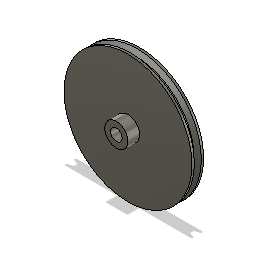
Support moteur (Autodesk Fusion 360 archive; units mm, degrees)
design "PouliePlastique"
Autodesk Fusion 360 part; units mm, degrees
sketch "Esquisse1" plane through (0, 0, 0) normal (1, 0, 0) x (0, 0, -1)
  line L0 (0, 0) -> (33, 0) construction
  line L1 (0, 0) -> (0, 20) construction
  line L2 (-10, 0) -> (-10, 110)
  line L3 (-10, 110) -> (-6, 110)
  line L4 (-6, 110) -> (-3, 100.5)
  line L5 (-3, 100.5) -> (0, 100.5)
  line L6 (3, 100.5) -> (0, 100.5)
  line L7 (10, 0) -> (10, 110)
  line L8 (6, 110) -> (3, 100.5)
  line L9 (10, 110) -> (6, 110)
  line L10 (10, 0) -> (-10, 0)
  point P0 (0, 20)
  dimension "d7" = 110
  dimension "d8" = 4
  dimension "d9" = 100.5
  dimension "d11" = 3
  dimension "d21" = 107.526
  constraint coincident L0.start L1.start
  constraint horizontal L0
  constraint perpendicular L0 L1
  constraint vertical L2
  constraint perpendicular L2 L3
  constraint horizontal L5
  constraint coincident L1 L5.end
  constraint coincident L0 L2.start
  constraint symmetric L0.start L1 origin
  constraint symmetric P0 L1 L1.end
  constraint symmetric L1 L2.start L7.start
  constraint symmetric L1 L2.end L7.end
  constraint symmetric L1 L3.end L8.start
  constraint symmetric L1 L4.end L6.start
  constraint symmetric L1 L5.end L6.end
  measures "d7" distance of L2.start L2.end
  measures "d8" distance of L2.end L3.end
  measures "d9" distance of L2.start L5
  measures "d11" distance of L4.end L5.end
  measures "d21" angle of L4 L5
revolve "Révolution1" add sketch "Esquisse1" angle 360 about axis through (0, 0, 0) along (0, 0, -1)
sketch "Esquisse2" plane through (0, 0, 10) normal (0, 0, 1) x (1, 0, 0)
  circle A0 centre (0, 0) radius 110
  circle A1 centre (0, 0) radius 20
  dimension "d14" = 40
  constraint concentric A0 A1
  measures "d14" diameter of A1
extrude "Extrusion1" add sketch "Esquisse2" along normal blind 20 contours A1
sketch "Esquisse3" plane through (0, 0, 30) normal (0, 0, 1) x (1, 0, 0)
  circle A0 centre (0, 0) radius 20
  circle A1 centre (0, 0) radius 10
  dimension "d17" = 20
  constraint concentric A0 A1
  measures "d17" diameter of A1
extrude "Extrusion2" cut sketch "Esquisse3" against normal up to surface (40 mm away) contours A1
sketch "Esquisse4" plane through (0, 0, -10) normal (0, 0, -1) x (-1, 0, 0)
  circle A0 centre (0, 0) radius 10
  circle A1 centre (0, 0) radius 110
  circle A2 centre (0, 0) radius 98
  dimension "d23" = 196
  constraint coincident A0.centre A1.centre
  measures "d23" diameter of A2
extrude "Extrusion3" cut sketch "Esquisse4" against normal blind 5 draft -45 contours A2
equation "DiamInt = DiamExt - 19 mm"
equation "DiamExt = 220 mm"
equation "EpGrande = 16 mm"
equation "EpPetit = 20 mm"
equation "PetitDiam = 40 mm"
equation "Alesage = 20 mm"
equation "d7 = DiamExt / 2"
equation "d8 = epParoiTrapeze"
equation "d9 = DiamInt / 2"
equation "d11 = distFond / 2"
equation "distFond = 6 mm"
equation "d14 = PetitDiam"
equation "d15 = EpPetit"
equation "d17 = Alesage"
equation "epParoiTrapeze = 4 mm"
equation "d23 = DiamInt - 5 mm"

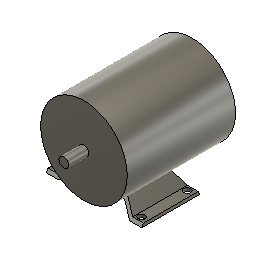
design "Moteur 103"
Autodesk Fusion 360 part; units mm, degrees
sketch "Esquisse1" plane through (0, 0, 0) normal (0, 0, 1) x (1, 0, 0)
  line L0 (-145.8621, 0) -> (174.312, 0) construction
  line L1 (0, -110) -> (0, 130) construction
  circle A0 centre (0, 59.5) radius 53.5
  dimension "d12" = 107
  dimension "d13" = 59.5
  constraint horizontal L0
  constraint perpendicular L0 L1
  constraint coincident L1 A0.centre
  measures "d12" diameter of A0
  measures "d13" distance of L0 A0.centre
ref_plane "Plan de construction1" through (0, 59.5, -12.5) normal (0, 0, 1) x (1, 0, 0)
sketch "Esquisse2" plane through (0, 0, -12.5) normal (0, 0, 1) x (1, 0, 0)
  line L0 (-59, 4) -> (-45.6569, 4)
  line L1 (-45.6569, 4) -> (-32.5871, 17.0697)
  line L2 (-32.5871, 17.0697) -> (32.5871, 17.0697)
  line L3 (32.5871, 17.0697) -> (45.6569, 4)
  line L4 (45.6569, 4) -> (59, 4)
  line L5 (59, 4) -> (59, 0)
  line L6 (59, 0) -> (44, 0)
  line L7 (44, 0) -> (30.9303, 13.0697)
  line L8 (30.9303, 13.0697) -> (-30.9303, 13.0697)
  line L9 (-30.9303, 13.0697) -> (-44, 0)
  line L10 (-44, 0) -> (-59, 0)
  line L11 (-59, 0) -> (-59, 4)
  line L12 (0, -110) -> (0, 130)
  circle A0 centre (0, 59.5) radius 53.5
  line L13 (-145.8621, 0) -> (174.312, 0)
  dimension "d15" = 4
  dimension "d16" = 4
  dimension "d17" = 4
  dimension "d18" = 4
  dimension "d19" = 4
  dimension "d20" = 118
  dimension "d23" = 15
  dimension "d24" = 15
  dimension "d25" = 45
  constraint horizontal L0
  constraint parallel L0 L2
  constraint parallel L2 L4
  constraint perpendicular L4 L5
  constraint perpendicular L5 L6
  constraint parallel L6 L8
  constraint horizontal L10
  constraint parallel L3 L7
  constraint parallel L1 L9
  constraint vertical L11
  constraint symmetric L5 L11 L12
  constraint coincident L1.end A0
  constraint coincident L2.end A0
  constraint collinear L6 L13
  constraint collinear L10 L13
  measures "d15" distance of L0 L10
  measures "d16" distance of L4 L6
  measures "d17" distance of L3 L7
  measures "d18" distance of L1 L9
  measures "d19" distance of L2 L8
  measures "d20" distance of L5 L11
  measures "d23" distance of L9.end L10.end
  measures "d24" distance of L5.end L6.end
  measures "d25" angle of L9 L13
extrude "Extrusion1" add sketch "Esquisse2" against normal blind 72 contours L0 L1 L8 L9 L10 L11 A0 L13 | L2 L8 L12 A0 | L2 L8 L12 A0 | L3 L4 L5 L6 L7 L8 A0 L13 makes body 1
extrude "Extrusion2" add sketch "Esquisse1" against normal blind 134 separate body makes body 2
sketch "Esquisse3" plane through (0, 0, 0) normal (0, -1, 0) x (1, 0, 0)
  line L0 (-44, -12.5) -> (-59, -12.5)
  line L1 (-59, -12.5) -> (-59, -84.5)
  line L2 (-59, -84.5) -> (-44, -84.5)
  line L3 (-44, -84.5) -> (-44, -12.5)
  circle A0 centre (-51.25, -20.25) radius 4.25
  circle A1 centre (-51.25, -76.75) radius 4.25
  line L4 (-59, -48.5) -> (-101.7179, -48.5) construction
  line L5 (0, -30) -> (0, -86.942) construction
  circle A2 centre (51.25, -20.25) radius 4.25
  circle A3 centre (51.25, -76.75) radius 4.25
  dimension "d31" = 8.5
  dimension "d32" = 8.5
  dimension "d33" = 56.5
  dimension "d34" = 102.5
  constraint midpoint L1 L4.start
  constraint perpendicular L1 L4
  constraint symmetric A0 A1 L4
  constraint vertical L5
  constraint symmetric A0 L5 A2
  constraint symmetric A1 L5 A3
  measures "d31" diameter of A0
  measures "d32" diameter of A1
  measures "d33" vertical distance of A0.centre A1.centre
  measures "d34" distance of A0.centre A2.centre
extrude "Extrusion3" cut sketch "Esquisse3" against normal blind 4 contours A0 | A1 | A2 | A3 bodies 1
sketch "Esquisse4" plane through (0, 0, 0) normal (0, 0, 1) x (1, 0, 0)
  circle A0 centre (0, 59.5) radius 53.5
  circle A1 centre (0, 59.5) radius 6
  dimension "d37" = 12
  constraint concentric A0 A1
  measures "d37" diameter of A1
extrude "Extrusion4" add sketch "Esquisse4" along normal blind 25 contours A1 bodies 2
ref_plane "Plan de construction2" through (0, 59.5, 11) normal (0, 0, 1) x (1, 0, 0)
sketch "Esquisse5" plane through (0, 0, 11) normal (0, 0, 1) x (1, 0, 0)
  circle A0 centre (0, 59.5) radius 6
  circle A1 centre (0, 59.5) radius 16
  dimension "d42" = 32
  constraint concentric A0 A1
  measures "d42" diameter of A1
extrude "Extrusion5" add sketch "Esquisse5" along normal blind 4 separate body makes body 3
draft "Dépouille1" angle -28 neutral plane through (59, 0, -12.5) pull (0, -1, 0) 2 faces at (10.3101, 15.7364, -84.5) (10.3101, 15.7364, -12.5) on bodies 1
sketch "Esquisse6" plane through (0, 0, -134) normal (0, 0, -1) x (-1, 0, 0)
  circle A0 centre (0, 59.5) radius 53.5
  line L0 (0, 59.5) -> (62.6116, 59.5) construction
  line L1 (0, 59.5) -> (-63, 59.5) construction
  line L2 (-66.2919, 37.9605) -> (74.2104, 83.6124) construction
  circle A1 centre (-44.2241, 45.1307) radius 2.5
  circle A2 centre (44.2241, 73.8693) radius 2.5
  point P0 (-44.2241, 45.1307)
  point P1 (44.2241, 73.8693)
  point P2 (50.8815, 76.0324)
  point P3 (-50.8815, 42.9676)
  dimension "d48" = 18
  dimension "d49" = 7
  dimension "d50" = 7
  dimension "d51" = 5
  dimension "d52" = 5
  constraint coincident A0.centre L0.start
  constraint horizontal L0
  constraint parallel L0 L1
  constraint coincident A0.centre L2
  constraint coincident L2 P0
  constraint coincident L2 P1
  constraint coincident A0 P2
  constraint coincident L2 P2
  constraint coincident A0 P3
  constraint coincident L2 P3
  constraint coincident P0 A1.centre
  constraint coincident P1 A2.centre
  measures "d48" angle of L0 L2
  measures "d49" distance of P0 P3
  measures "d50" distance of P1 P2
  measures "d51" diameter of A1
  measures "d52" diameter of A2
extrude "Extrusion6" cut sketch "Esquisse6" against normal blind 7 contours A1 | A2 bodies 2
hidden bodies 3
equation "DiaMot = 107 mm"
equation "LongMot = 134 mm"
equation "EntreAxeAv = 94 mm + 8.5 mm"
equation "EntreAxLat = 48 mm + 8.5 mm"
equation "EpPied = 4 mm"
equation "HautMot = 6 mm"
equation "LargPiedSoud = 55 mm"
equation "DecalPiedMot = 21 mm - ( ( 72 - 55 ) / 2 ) * 1 mm"
equation "ContPiedSol = 15 mm"
equation "DecRoueMot = 14 mm"
equation "EpRoue = 4 mm"
equation "d12 = DiaMot"
equation "d13 = HautMot + DiaMot / 2"
equation "d14 = -DecalPiedMot"
equation "d15 = EpPied"
equation "d16 = EpPied"
equation "d17 = EpPied"
equation "d18 = EpPied"
equation "d19 = EpPied"
equation "d20 = ExtPiedAv"
equation "ExtPiedAv = 118 mm"
equation "ExtPiedCote = 72 mm"
equation "d23 = ContPiedSol"
equation "d24 = ContPiedSol"
equation "d26 = -ExtPiedCote"
equation "d28 = -LongMot"
equation "DiamTrou = 8.5 mm"
equation "d31 = DiamTrou"
equation "d32 = DiamTrou"
equation "d33 = EntreAxLat"
equation "d34 = EntreAxeAv"
equation "d37 = DiamAxeMot"
equation "d40 = -DecRoueMot"
equation "DiamRoueDent = 32 mm"
equation "d42 = DiamRoueDent"
equation "d43 = EpRoue"
equation "DiamAxeMot = 12 mm"
equation "d50 = d49"
equation "d52 = d51"

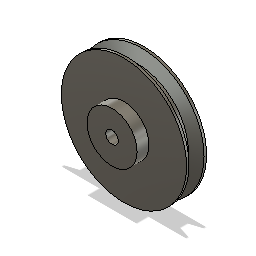
design "Poulie"
Autodesk Fusion 360 part; units mm, degrees
sketch "Esquisse1" plane through (0, 0, 0) normal (1, 0, 0) x (0, 0, -1)
  line L0 (0, 0) -> (33, 0) construction
  line L1 (0, 0) -> (0, 20) construction
  line L2 (-8, 0) -> (-8, 50)
  line L3 (-8, 50) -> (-6, 50)
  line L4 (-6, 50) -> (-3, 40.5)
  line L5 (-3, 40.5) -> (0, 40.5)
  line L6 (3, 40.5) -> (0, 40.5)
  line L7 (8, 0) -> (8, 50)
  line L8 (6, 50) -> (3, 40.5)
  line L9 (8, 50) -> (6, 50)
  line L10 (8, 0) -> (-8, 0)
  point P0 (0, 20)
  dimension "d7" = 50
  dimension "d8" = 2
  dimension "d9" = 40.5
  dimension "d10" = 5
  dimension "d11" = 3
  constraint coincident L0.start L1.start
  constraint horizontal L0
  constraint perpendicular L0 L1
  constraint vertical L2
  constraint perpendicular L2 L3
  constraint horizontal L5
  constraint coincident L1 L5.end
  constraint coincident L0 L2.start
  constraint symmetric L0.start L1 origin
  constraint symmetric P0 L1 L1.end
  constraint symmetric L1 L2.start L7.start
  constraint symmetric L1 L2.end L7.end
  constraint symmetric L1 L3.end L8.start
  constraint symmetric L1 L4.end L6.start
  constraint symmetric L1 L5.end L6.end
  measures "d7" distance of L2.start L2.end
  measures "d8" distance of L2.end L3.end
  measures "d9" distance of L2.start L5
  measures "d10" distance of L2 L4.end
  measures "d11" distance of L4.end L5.end
revolve "Révolution1" add sketch "Esquisse1" angle 360 about axis through (0, 0, 0) along (0, 0, -1)
sketch "Esquisse2" plane through (0, 0, 8) normal (0, 0, 1) x (1, 0, 0)
  circle A0 centre (0, 0) radius 50
  circle A1 centre (0, 0) radius 20
  dimension "d14" = 40
  constraint concentric A0 A1
  measures "d14" diameter of A1
extrude "Extrusion1" add sketch "Esquisse2" along normal blind 9.5 contours A1
sketch "Esquisse3" plane through (0, 0, 17.5) normal (0, 0, 1) x (1, 0, 0)
  circle A0 centre (0, 0) radius 20
  circle A1 centre (0, 0) radius 5
  dimension "d17" = 10
  constraint concentric A0 A1
  measures "d17" diameter of A1
extrude "Extrusion2" cut sketch "Esquisse3" against normal blind 25.5 contours A1
equation "DiamInt = DiamExt - 19 mm"
equation "DiamExt = 100 mm"
equation "EpGrande = 16 mm"
equation "EpPetit = 9.5 mm"
equation "PetitDiam = 40 mm"
equation "Alesage = 10 mm"
equation "d7 = DiamExt / 2"
equation "d9 = DiamInt / 2"
equation "d11 = distFond / 2"
equation "distFond = 6 mm"
equation "d14 = PetitDiam"
equation "d15 = EpPetit"
equation "d17 = Alesage"
